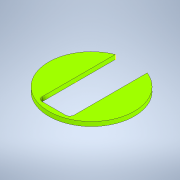
# Autodesk Inventor part: inglobare_baterie_6mm_
Saved by Autodesk Inventor 2022.6 (Build 266554000, 554)
## iProperties
Created: 2025-06-10
Part Number: inglobare_baterie_6mm_
Material: Generic
Document SubType Name: Modeling
Designer: Dragos Macovei
Density: 1 g/cm^3
Appearance: Default
Author: Dragos Macovei
Autodesk Inventor part; units mm, degrees
ref_plane "YZ Plane" through (0, 0, 0) normal (1, 0, 0) x (0, 1, 0)
ref_plane "XZ Plane" through (0, 0, 0) normal (0, 1, 0) x (-1, 0, 0)
ref_plane "XY Plane" through (0, 0, 0) normal (0, 0, 1) x (1, 0, 0)
sketch "Sketch1" plane through (0, 0, 0) normal (0, 1, 0) x (-1, 0, 0)
  arc A0 (22, -54.7449) -> (-22, -54.7449) centre (0, 0) ccw
  line L0 (22, 52) -> (-22, 52)
  line L1 (-22, 52) -> (-22, -50)
  line L2 (22, -50) -> (22, 52)
  line L3 (22, -50) -> (22, -54.7449)
  line L4 (-22, -50) -> (-22, -54.7449)
  line L5 (9.1086, 60.4581) -> (46.4066, 44.0287)
  line L6 (22, 52) -> (23.0254, 54.3279)
  point P0 (0, 59)
  dimension "d0" = 118
  dimension "d4" = 22
  dimension "d8" = 22
  dimension "d9" = 7
  constraints: 14 end point, 3 point on circle, 2 coincident, 2 perpendicular, 2 vertical, 1 centre point, 1 horizontal, 1 parallel, 1 point on line, 1 tangent
  measures "d0" diameter of A0
  measures "d4" distance from line of point (0, 0) L2
  measures "d8" distance from line of point (0, 0) L1
  measures "d9" distance from line of point (0, 59) L0
extrude "Extrusion1" add sketch "Sketch1" along normal blind 6 contours L3 L2 L6 A0 | L6 L0 L1 L4 A0
fillet "Fillet1" radius 6 2 edges at (-22, 3, 52) (22, 3, 52)
sketch "Sketch2" plane through (-22, 0, -54.7449) normal (1, 0, 0) x (0, 0, -1)
  line L0 (0, 0) -> (0, 0) projected
  line L1 (0, 0) -> (0, 6) projected
  line L2 (0, 6) -> (0, 6) projected
  line L3 (0, 0) -> (0, 6) projected
  point P0 (-54.7449, 0)
body "Solid1"
